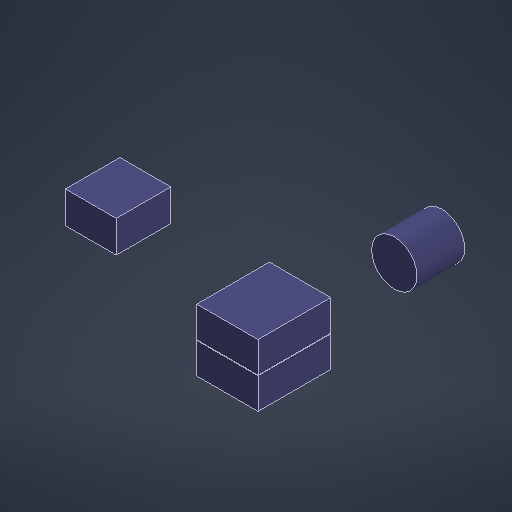
# Autodesk Inventor part: ref_tall
Saved by Autodesk Inventor 2027.1 (Build 311270010, 270A)
## iProperties
Created: 2026-10-22
Part Number: ref_tall
Material: 일반
Document SubType Name: Modeling
Designer: sungjun
Density: 1 g/cm^3
Appearance: ref_tall_c
Author: sungjun
Autodesk Inventor part; units mm, degrees
ref_plane "작업 평면1" through (0, 0, 13.35) normal (0, 0, 1) x (1, 0, 0)
sketch "스케치1" plane through (0, 0, 13.35) normal (0, 0, 1) x (1, 0, 0)
  circle A0 centre (74.5, 54) radius 5
  constraints: 1 centre point
extrude "돌출1" add sketch "스케치1" along normal mid plane 10.5
ref_plane "작업 평면2" through (0, 0, 14.1) normal (0, 0, 1) x (1, 0, 0)
sketch "스케치2" plane through (0, 0, 14.1) normal (0, 0, 1) x (1, 0, 0)
  line L0 (3.6, 26.4) -> (14.8, 26.4)
  line L1 (14.8, 26.4) -> (14.8, 33.4)
  line L2 (14.8, 33.4) -> (3.6, 33.4)
  line L3 (3.6, 33.4) -> (3.6, 26.4)
  constraints: 8 end point, 2 parallel, 1 horizontal, 1 perpendicular
extrude "돌출2" add sketch "스케치2" along normal mid plane 12
ref_plane "작업 평면3" through (0, 0, 16.1) normal (0, 0, 1) x (1, 0, 0)
sketch "스케치3" plane through (0, 0, 16.1) normal (0, 0, 1) x (1, 0, 0)
  line L0 (36.5, 23.1) -> (50, 23.1)
  line L1 (50, 23.1) -> (50, 29.9)
  line L2 (50, 29.9) -> (36.5, 29.9)
  line L3 (36.5, 29.9) -> (36.5, 23.1)
  constraints: 8 end point, 2 parallel, 1 horizontal, 1 perpendicular
extrude "돌출3" add sketch "스케치3" along normal mid plane 16
ref_plane "작업 평면4" through (0, 0, 16.1) normal (0, 0, 1) x (1, 0, 0)
sketch "스케치4" plane through (0, 0, 16.1) normal (0, 0, 1) x (1, 0, 0)
  line L0 (36.5, 16.2) -> (50, 16.2)
  line L1 (50, 16.2) -> (50, 23)
  line L2 (50, 23) -> (36.5, 23)
  line L3 (36.5, 23) -> (36.5, 16.2)
  constraints: 8 end point, 2 parallel, 1 horizontal, 1 perpendicular
extrude "돌출4" add sketch "스케치4" along normal mid plane 16
